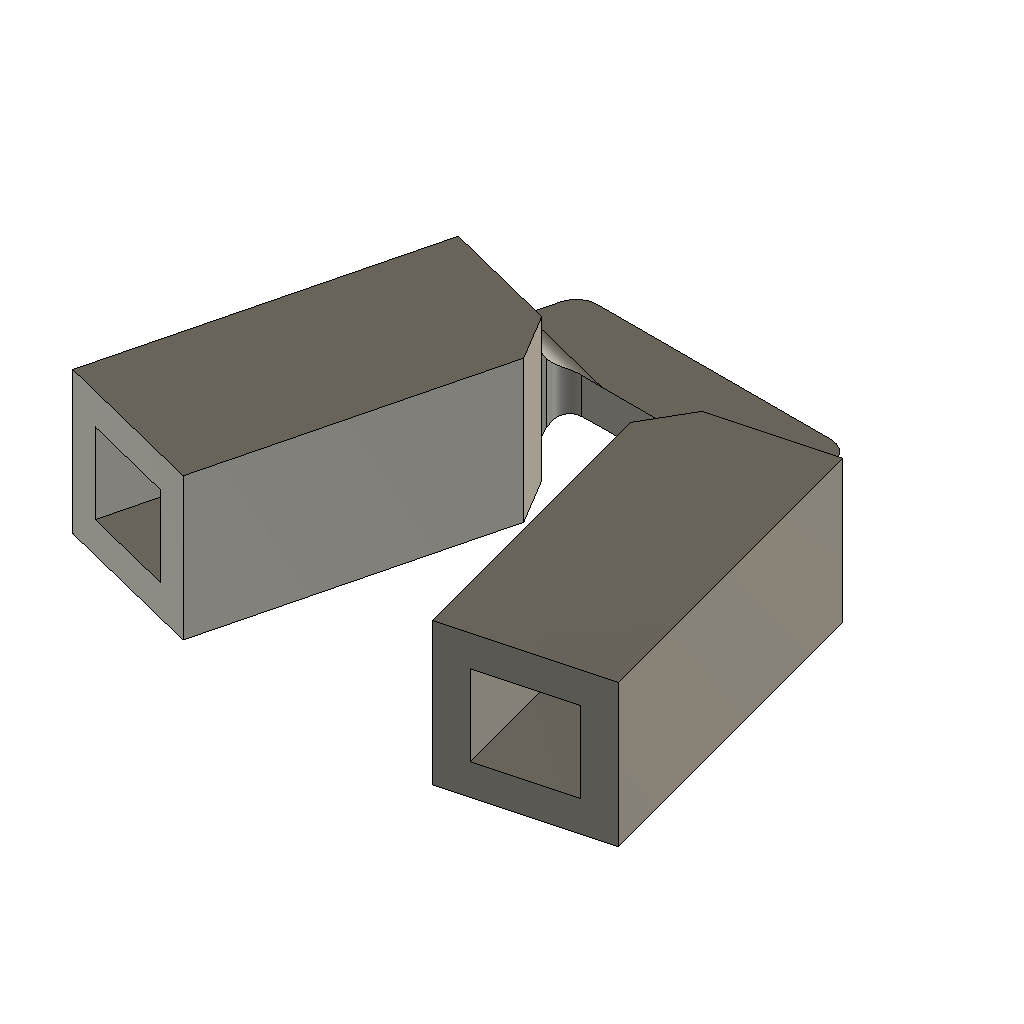
ID.3 Mirror Hook (Autodesk Fusion 360 design; units mm, degrees)
part number: 2026-09-29-20-49-33-204
Autodesk Fusion 360 part; units mm, degrees
sketch "Sketch1" plane through (0, 0, 0) normal (0, 0, 1) x (1, 0, 0)
  line L0 (0, 0) -> (3.7521, 14.9623)
  line L1 (4.7925, 16) -> (10.945, 16)
  line L2 (11.9109, 15.2588) -> (16, 0)
  line L3 (16, 0) -> (0, 0) construction
  line L4 (0.4833, 15.782) -> (1.1933, 18.6132)
  line L5 (2.1632, 19.37) -> (13.5308, 19.37)
  line L6 (14.4967, 18.6288) -> (19.2551, 0.8723)
  line L7 (-3.2688, 0.8197) -> (0, 0)
  line L8 (16, 0) -> (19.2551, 0.8723)
  arc A0 (2.1632, 19.37) -> (1.1933, 18.6132) centre (2.1632, 18.37) ccw
  arc A1 (14.4967, 18.6288) -> (13.5308, 19.37) centre (13.5308, 18.37) ccw
  arc A2 (11.9109, 15.2588) -> (10.945, 16) centre (10.945, 15) ccw
  arc A3 (4.7925, 16) -> (3.8225, 15.2432) centre (4.7925, 15) ccw
  line L9 (12.0144, 14.8726) -> (15.2695, 15.745) construction
  line L10 (3.7521, 14.9623) -> (0.4833, 15.782) construction
  line L11 (3.7521, 14.9623) -> (3.8225, 15.2432)
  line L12 (-3.2688, 0.8197) -> (0.4833, 15.782)
  line L13 (12.0144, 14.8726) -> (15.2695, 15.745)
  line L14 (3.7521, 14.9623) -> (0.4833, 15.782)
  point P0 (4.0123, 16)
  point P1 (11.7123, 16)
  dimension "d1" = 7.7
  dimension "d3" = 16
  dimension "d4" = 16
  dimension "d5" = 16
  dimension "d7" = 3.37
  dimension "d8" = 3.37
  dimension "d9" = 3.37
  dimension "d10" = 1
  constraint coincident L0.start L3.end
  constraint horizontal L1
  constraint perpendicular L0 L7
  constraint perpendicular L6 L8
  constraint tangent L5 A0
  constraint tangent L4 A0
  constraint tangent L6 A1
  constraint tangent L5 A1
  constraint equal A0 A1
  constraint coincident P1 L1
  constraint coincident P1 L2
  constraint tangent L1 A2
  constraint tangent L2 A2
  constraint equal A0 A2
  constraint coincident P0 L0
  constraint coincident P0 L1
  constraint tangent L0 A3
  constraint tangent L1 A3
  constraint equal A0 A3
  constraint coincident L2 L9.start
  constraint coincident L6 L9.end
  constraint perpendicular L4 L10
  constraint perpendicular L2 L9
  constraint perpendicular L7 L11
  constraint tangent A0 L12
  measures "d1" distance of P0 P1
  measures "d3" distance of L0.start L2.end
  measures "d4" vertical distance of P1 L2.end
  measures "d5" vertical distance of L0.start P0
  measures "d7" distance of L0 L4
  measures "d8" distance of L1 L5
  measures "d9" distance of L2 L6
  measures "d10" radius of A0
extrude "Extrude2" add sketch "Sketch1" along normal blind 1.7 contours L1 L2 L4 L5 L6 A0 A1 A2 A3 L11 L13 L14 makes body 1
extrude "Extrude3" add sketch "Sketch1" along normal blind 2.3 and the other way blind 0.6 contours L0 L7 L12 L14 | L2 L6 L8 L13 bodies 1
sketch "Sketch4" plane through (0, 0, 0) normal (-0.243237, -0.969967, 0) x (0.969967, -0.243237, 0)
  line L0 (0, -0.6) -> (0, 2.3)
  line L1 (0, 2.3) -> (-3.37, 2.3)
  line L2 (-3.37, 2.3) -> (-3.37, -0.6)
  line L3 (-3.37, -0.6) -> (0, -0.6)
  line L4 (-3.37, 2.3) -> (0, -0.6) construction
  line L5 (0, 2.3) -> (-3.37, -0.6) construction
  line L6 (2, 4.3) -> (-5.37, 4.3)
  line L7 (-5.37, 4.3) -> (-5.37, -2.6)
  line L8 (-5.37, -2.6) -> (2, -2.6)
  line L9 (2, -2.6) -> (2, 4.3)
  line L10 (2, 4.3) -> (-5.37, -2.6) construction
  line L11 (-5.37, 4.3) -> (2, -2.6) construction
  point P0 (-1.685, 0.85)
  dimension "d30" = 2
  dimension "d31" = 2
  constraint coincident L1.end L2.start
  constraint coincident L0.start L3.end
  constraint coincident L0.end L1.start
  constraint coincident L2.end L3.start
  constraint horizontal L6
  constraint perpendicular L6 L7
  constraint parallel L6 L8
  constraint parallel L7 L9
  constraint coincident L10 P0
  constraint coincident L11 P0
  constraint midpoint L4 P0
  measures "d30" distance of L2 L7
  measures "d31" distance of L3 L8
sketch "Sketch5" plane through (1.072, -4.0004, 0) normal (0.258849, -0.965918, 0) x (0.965918, 0.258849, 0)
  line L0 (18.8247, -0.6) -> (18.8247, 2.3)
  line L1 (18.8247, 2.3) -> (15.4547, 2.3)
  line L2 (15.4547, 2.3) -> (15.4547, -0.6)
  line L3 (15.4547, -0.6) -> (18.8247, -0.6)
  line L4 (15.4547, 2.3) -> (18.8247, -0.6) construction
  line L5 (18.8247, 2.3) -> (15.4547, -0.6) construction
  line L6 (20.8247, 4.3) -> (13.4547, 4.3)
  line L7 (13.4547, 4.3) -> (13.4547, -2.6)
  line L8 (13.4547, -2.6) -> (20.8247, -2.6)
  line L9 (20.8247, -2.6) -> (20.8247, 4.3)
  line L10 (20.8247, 4.3) -> (13.4547, -2.6) construction
  line L11 (13.4547, 4.3) -> (20.8247, -2.6) construction
  point P0 (17.1397, 0.85)
  dimension "d32" = 2
  dimension "d33" = 2
  constraint coincident L1.end L2.start
  constraint coincident L0.start L3.end
  constraint coincident L0.end L1.start
  constraint coincident L2.end L3.start
  constraint horizontal L6
  constraint perpendicular L6 L7
  constraint parallel L6 L8
  constraint parallel L7 L9
  constraint coincident L10 P0
  constraint coincident L11 P0
  constraint midpoint L4 P0
  measures "d32" distance of L0 L9
  measures "d33" distance of L3 L8
extrude "Extrude6" add sketch "Sketch5" against normal up to surface (15.3974 mm away) separate body makes body 2
extrude "Extrude7" add sketch "Sketch4" against normal up to surface (15.4255 mm away) separate body makes body 3
move_face "OffsetFaces2" offset -15 1 faces at (18.1701, 0.5815, 1.3333) on bodies 1
move_face "OffsetFaces3" offset -15 1 faces at (-1.0896, 0.2732, 1.3333) on bodies 1
combine "Combine1" operation add target body 3 tool bodies 1 2
move_face "OffsetFaces4" offset -0.5 8 faces at (15.7908, 5.1204, -0.6) (17.9609, 5.7019, 0.3667) (-2.0526, 5.6695, 1.3333) (0.2532, 10.2461, -0.6) (1.2162, 4.8498, 0.3667) (0.1266, 5.1231, 2.3) (16.8759, 5.4111, 2.3) (14.7058, 4.8296, 1.3333) on bodies 3
fillet "Fillet1" radius 1.5 6 edges at (13.642, 15.3088, 1.7) (2.1177, 15.3721, 1.7) (2.1177, 15.3721, 0) (13.642, 15.3088, 0) (15.2695, 15.745, 0.85) (0.4833, 15.782, 0.85) on bodies 3
chamfer "Chamfer1" distance 1.8 angle 45 2 edges at (10.0826, 14.3549, 0.85) (5.692, 14.4758, 0.85) tangent chain off on bodies 3
